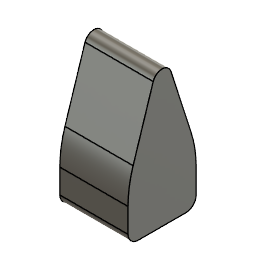
audio amplifier_assembly (Autodesk Fusion 360 archive; units mm, degrees)
design "slide potentiometer knob"
Autodesk Fusion 360 part; units mm, degrees
sketch "Sketch1" plane through (0, 0, 0) normal (0, 1, 0) x (1, 0, 0)
  line L0 (0, 0) -> (10, 0)
  line L1 (10, 0) -> (10, 10)
  line L2 (10, 10) -> (0, 10)
  line L3 (0, 10) -> (0, 0)
  dimension "d1" = 10
  dimension "d2" = 10
  constraint horizontal L0
  constraint vertical L1
  constraint horizontal L2
  constraint vertical L3
  constraint coincident L0.start L3.end
  measures "d1" distance of L0.start L0.end
  measures "d2" distance of L0.start L2.end
extrude "Extrude1" add sketch "Sketch1" along normal blind 20
chamfer "Chamfer1" distance 4 distance2 12.5 2 edges at (5, 20, 0) (5, 20, -10) measured on face at (3.3333, 20, -6.6667) measured on face at (3.3333, 20, -6.6667) tangent chain off
fillet "Fillet1" radius 1.37 2 edges at (5, 20, -6) (5, 20, -4)
fillet "Fillet2" radius 15.75 2 edges at (5, 7.5, 0) (5, 7.5, -10)
sketch "Sketch2" plane through (0, 0, 0) normal (0, -1, 0) x (1, 0, 0)
  line L0 (0, 0) -> (0, -10)
  line L1 (0, -10) -> (10, -10)
  line L2 (10, -10) -> (10, 0)
  line L3 (10, 0) -> (0, 0)
  line L4 (4.35, -2.95) -> (5.65, -2.95)
  line L5 (5.65, -2.95) -> (5.65, -7.05)
  line L6 (5.65, -7.05) -> (4.35, -7.05)
  line L7 (4.35, -7.05) -> (4.35, -2.95)
  dimension "d11" = 1.3
  dimension "d12" = 4.1
  dimension "d13" = 4.35
  dimension "d14" = 4.35
  dimension "d15" = 2.95
  dimension "d16" = 2.95
  constraint horizontal L4
  constraint vertical L5
  constraint horizontal L6
  constraint vertical L7
  measures "d11" distance of L4.start L4.end
  measures "d12" distance of L4.start L6.end
  measures "d13" distance of L2 L5
  measures "d14" distance of L0 L7
  measures "d15" distance of L3 L4
  measures "d16" distance of L1 L6
extrude "Extrude2" cut sketch "Sketch2" against normal blind 15 contours L4 L5 L6 L7
chamfer "Chamfer2" distance 1 angle 45 4 edges at (5.65, 0, -5) (5, 0, -2.95) (4.35, 0, -5) (5, 0, -7.05) tangent chain off
fillet "Fillet3" radius 1.5 2 edges at (5, 0, -10) (5, 0, 0)
